Orange_UpperLeg_Tactical_v2 (Autodesk Fusion 360 design; units mm, degrees)
part number: 2026-11-06-02-17-48-614
Autodesk Fusion 360 part; units mm, degrees
ref_plane "WorkPlane1" through (0, 34.28, 0) normal (0, 1, 0) x (0, 0, 1)
sketch "HipShield" plane through (0, 34.28, 0) normal (0, 1, 0) x (1, 0, 0)
  line L0 (-12.447, 47.15) -> (-12.447, 26)
  line L1 (-12.447, 26) -> (-3.5, 16.67)
  line L2 (-3.5, 16.67) -> (4.16, 16.67)
  line L3 (4.16, 16.67) -> (7.87, 20.38)
  line L4 (7.87, 20.38) -> (7.87, 47.15)
  line L5 (7.87, 47.15) -> (-12.447, 47.15)
extrude "HipShield (1)" add sketch "HipShield" along normal blind 5.078 makes body 1
ref_plane "WorkPlane2" through (-12.447, 0, 0) normal (1, 0, 0) x (0, 1, 0)
sketch "ThighPanel" plane through (-12.447, 0, 0) normal (1, 0, 0) x (0, 0, -1)
  line L0 (66.2, 17.86) -> (56, 39.358)
  line L1 (56, 39.358) -> (42.07, 39.358)
  line L2 (42.07, 39.358) -> (42.07, 25)
  line L3 (42.07, 25) -> (39.31, 19.5)
  line L4 (39.31, 19.5) -> (39.31, 11.6)
  line L5 (39.31, 11.6) -> (44, 8.88)
  line L6 (44, 8.88) -> (62.48, 8.88)
  line L7 (62.48, 8.88) -> (66.2, 12.6)
  line L8 (66.2, 12.6) -> (66.2, 17.86)
extrude "ThighPanel (1)" add sketch "ThighPanel" along normal blind 5.077 bodies 1
ref_plane "WorkPlane3" through (0, 0, -47.15) normal (0, 0, 1) x (1, 0, 0)
sketch "InnerWeb" plane through (0, 0, -47.15) normal (0, 0, 1) x (1, 0, 0)
  line L0 (-7.37, 20) -> (-7.37, 36)
  line L1 (-7.37, 36) -> (7.87, 36)
  line L2 (7.87, 36) -> (7.87, 34.28)
  line L3 (7.87, 34.28) -> (-7.37, 20)
extrude "InnerWeb (1)" add sketch "InnerWeb" along normal blind 5.08 bodies 1
fillet "InnerCornerR2" radius 2 1 edges at (-2.2885, 34.28, -42.07) on bodies 1
ref_plane "WorkPlane4" through (-9.691, 0, 0) normal (1, 0, 0) x (0, 1, 0)
sketch "KneePocketSlot" plane through (-9.691, 0, 0) normal (1, 0, 0) x (0, 0, -1)
  arc A0 (59.5197, 11.6504) -> (59.5039, 19.1542) centre (59.8276, 15.403) ccw
  arc A1 (43.2874, 17.7552) -> (43.2975, 12.9812) centre (43.4933, 15.3687) ccw
  line L0 (59.5039, 19.1542) -> (43.2874, 17.7552)
  line L1 (43.2975, 12.9812) -> (59.5197, 11.6504)
extrude "KneePocketSlot (1)" cut sketch "KneePocketSlot" along normal blind 19.691 bodies 1
ref_plane "WorkPlane5" through (0, 30, 0) normal (0, 1, 0) x (0, 0, 1)
sketch "HipPocket" plane through (0, 30, 0) normal (0, 1, 0) x (1, 0, 0)
  arc A0 (-2.467, 23.3477) -> (5.5136, 23.3479) centre (1.5233, 23.0168) ccw
  arc A1 (4.166, 39.5876) -> (-1.1203, 39.5874) centre (1.5229, 39.3682) ccw
  line L0 (-2.467, 23.3477) -> (-1.1203, 39.5874)
  line L1 (4.166, 39.5876) -> (5.5136, 23.3479)
extrude "HipPocket (1)" cut sketch "HipPocket" along normal blind 6.691 bodies 1
ref_plane "WorkPlane6" through (1.52, 0, 0) normal (1, 0, 0) x (0, 1, 0)
sketch "HipHubRev" plane through (1.52, 0, 0) normal (1, 0, 0) x (0, 0, -1)
  line L0 (23.02, 36.691) -> (23.02, 37.834)
  line L1 (23.02, 37.834) -> (29.36, 37.834)
  line L2 (29.36, 37.834) -> (29.52, 37.667)
  line L3 (29.52, 37.667) -> (29.72, 37.472)
  line L4 (29.72, 37.472) -> (29.92, 37.317)
  line L5 (29.92, 37.317) -> (30.12, 37.178)
  line L6 (30.12, 37.178) -> (30.32, 37.066)
  line L7 (30.32, 37.066) -> (30.52, 36.965)
  line L8 (30.52, 36.965) -> (30.72, 36.889)
  line L9 (30.72, 36.889) -> (30.92, 36.818)
  line L10 (30.92, 36.818) -> (31.22, 36.751)
  line L11 (31.22, 36.751) -> (31.52, 36.711)
  line L12 (31.52, 36.711) -> (31.82, 36.691)
  line L13 (31.82, 36.691) -> (31.82, 36.691)
  line L14 (31.82, 36.691) -> (23.02, 36.691)
  line L15 (23.02, 30) -> (23.02, 45) construction
revolve "HipHubRev (1)" add sketch "HipHubRev" angle 360 about axis through (1.52, 30, -23.02) along (0, 1, 0) separate body makes body 2
ref_plane "WorkPlane7" through (0, 36, 0) normal (0, 1, 0) x (0, 0, 1)
sketch "HipHubPrism" plane through (0, 36, 0) normal (0, 1, 0) x (1, 0, 0)
  arc A0 (-2.467, 23.3477) -> (5.5136, 23.3479) centre (1.5233, 23.0168) ccw
  arc A1 (4.166, 39.5876) -> (-1.1203, 39.5874) centre (1.5229, 39.3682) ccw
  line L0 (-2.467, 23.3477) -> (-1.1203, 39.5874)
  line L1 (4.166, 39.5876) -> (5.5136, 23.3479)
extrude "HipHubPrism (1)" add sketch "HipHubPrism" along normal blind 2.2 separate body makes body 3
combine "HipHubIntersect" operation intersect target body 2 tool bodies 3
combine "HipHubCut" operation cut target body 1 tool bodies 2
ref_plane "WorkPlane8" through (0, 15.41, 0) normal (0, 1, 0) x (0, 0, 1)
sketch "KneeHubRev" plane through (0, 15.41, 0) normal (0, 1, 0) x (1, 0, 0)
  line L0 (-9.691, 59.85) -> (-10.834, 59.85)
  line L1 (-10.834, 59.85) -> (-10.834, 53.51)
  line L2 (-10.834, 53.51) -> (-10.667, 53.35)
  line L3 (-10.667, 53.35) -> (-10.472, 53.15)
  line L4 (-10.472, 53.15) -> (-10.317, 52.95)
  line L5 (-10.317, 52.95) -> (-10.178, 52.75)
  line L6 (-10.178, 52.75) -> (-10.066, 52.55)
  line L7 (-10.066, 52.55) -> (-9.965, 52.35)
  line L8 (-9.965, 52.35) -> (-9.889, 52.15)
  line L9 (-9.889, 52.15) -> (-9.818, 51.95)
  line L10 (-9.818, 51.95) -> (-9.751, 51.65)
  line L11 (-9.751, 51.65) -> (-9.711, 51.35)
  line L12 (-9.711, 51.35) -> (-9.691, 51.05)
  line L13 (-9.691, 51.05) -> (-9.691, 51.05)
  line L14 (-9.691, 51.05) -> (-9.691, 59.85)
  line L15 (-14, 59.85) -> (-5, 59.85) construction
revolve "KneeHubRev (1)" add sketch "KneeHubRev" angle 360 about axis through (-14, 15.41, -59.85) along (1, 0, 0) separate body makes body 4
ref_plane "WorkPlane9" through (-9.2, 0, 0) normal (1, 0, 0) x (0, 1, 0)
sketch "KneeHubPrism" plane through (-9.2, 0, 0) normal (1, 0, 0) x (0, 0, -1)
  arc A0 (59.5197, 11.6504) -> (59.5039, 19.1542) centre (59.8276, 15.403) ccw
  arc A1 (43.2874, 17.7552) -> (43.2975, 12.9812) centre (43.4933, 15.3687) ccw
  line L0 (59.5039, 19.1542) -> (43.2874, 17.7552)
  line L1 (43.2975, 12.9812) -> (59.5197, 11.6504)
extrude "KneeHubPrism (1)" add sketch "KneeHubPrism" against normal blind 2 separate body makes body 5
combine "KneeHubIntersect" operation intersect target body 4 tool bodies 5
combine "KneeHubCut" operation cut target body 1 tool bodies 4
fillet "HipMouthR125" radius 1.25 30 edges at (-1.0887, 34.28, -39.8307) (-1.7936, 34.28, -31.4676) (1.5234, 34.28, -19.0128) (4.8398, 34.28, -31.4677) (4.1345, 34.28, -39.8308) (1.5229, 32.7224, -42.0205) (-1.7936, 34.28, -31.4676) (1.5234, 34.28, -19.0128) (4.8398, 34.28, -31.4677) (4.1345, 34.28, -39.8308) (1.5229, 32.7224, -42.0205) (-1.0887, 34.28, -39.8307) (1.5234, 34.28, -19.0128) (4.8398, 34.28, -31.4677) (4.1345, 34.28, -39.8308) (1.5229, 32.7224, -42.0205) (-1.0887, 34.28, -39.8307) (-1.7936, 34.28, -31.4676) (4.8398, 34.28, -31.4677) (4.1345, 34.28, -39.8308) (1.5229, 32.7224, -42.0205) (-1.0887, 34.28, -39.8307) (-1.7936, 34.28, -31.4676) (1.5234, 34.28, -19.0128) (4.1345, 34.28, -39.8308) (1.5229, 32.7224, -42.0205) (-1.0887, 34.28, -39.8307) (-1.7936, 34.28, -31.4676) (1.5234, 34.28, -19.0128) (4.8398, 34.28, -31.4677) on bodies 1
fillet "KneeMouthR125" radius 1.25 16 edges at (-7.37, 15.3636, -41.0979) (-7.37, 18.4547, -51.3957) (-7.37, 15.4109, -63.5927) (-7.37, 12.3158, -51.4086) (-7.37, 18.4547, -51.3957) (-7.37, 15.4109, -63.5927) (-7.37, 12.3158, -51.4086) (-7.37, 15.3636, -41.0979) (-7.37, 15.4109, -63.5927) (-7.37, 12.3158, -51.4086) (-7.37, 15.3636, -41.0979) (-7.37, 18.4547, -51.3957) (-7.37, 12.3158, -51.4086) (-7.37, 15.3636, -41.0979) (-7.37, 18.4547, -51.3957) (-7.37, 15.4109, -63.5927) on bodies 1
chamfer "BottomRightBevel" distance 4 angle 45 2 edges at (0.25, 27.14, -47.15) (7.87, 36.819, -47.15) tangent chain off on bodies 1
chamfer "BladeBevels" distance 1.4 angle 45 20 edges at (5.87, 39.358, -45.15) (-1.75, 39.358, -47.15) (-7.37, 39.358, -51.575) (-9.9085, 39.358, -56) (-12.447, 39.358, -41) (-7.9735, 39.358, -21.335) (0.33, 39.358, -16.67) (6.015, 39.358, -18.525) (7.87, 39.358, -31.765) (-12.447, 34.28, -33.035) (-12.447, 36.819, -26) (-12.447, 28.609, -61.1) (-12.447, 15.23, -66.2) (-12.447, 10.74, -64.34) (-12.447, 8.88, -53.24) (-12.447, 10.24, -41.655) (-12.447, 15.55, -39.31) (-12.447, 22.25, -40.69) (-12.447, 28.64, -42.07) (-12.447, 33.6942, -41.4842) tangent chain off on bodies 1
ref_plane "WorkPlane10" through (-13.447, 0, 0) normal (1, 0, 0) x (0, 1, 0)
sketch "PanelWindow0" plane through (-13.447, 0, 0) normal (1, 0, 0) x (0, 0, -1)
  line L0 (48, 34.066) -> (56.896, 24.246)
  line L1 (56.896, 24.246) -> (48, 22.4)
  line L2 (48, 22.4) -> (48, 34.066)
extrude "PanelWindow0 (1)" cut sketch "PanelWindow0" along normal blind 6.077 bodies 1
ref_plane "WorkPlane11" through (-13.447, 0, 0) normal (1, 0, 0) x (0, 1, 0)
sketch "PanelWindow1" plane through (-13.447, 0, 0) normal (1, 0, 0) x (0, 0, -1)
  line L0 (53.1, 36.3) -> (56.417, 29.243)
  line L1 (56.417, 29.243) -> (50.024, 36.3)
  line L2 (50.024, 36.3) -> (53.1, 36.3)
extrude "PanelWindow1 (1)" cut sketch "PanelWindow1" along normal blind 6.077 bodies 1
ref_plane "WorkPlane12" through (0, 30, 0) normal (0, 1, 0) x (0, 0, 1)
sketch "HipHoleC" plane through (0, 30, 0) normal (0, 1, 0) x (1, 0, 0)
  circle A0 centre (1.52, 23.02) radius 1.248
extrude "HipHoleC (1)" cut sketch "HipHoleC" along normal blind 11 bodies 1
ref_plane "WorkPlane13" through (0, 30, 0) normal (0, 1, 0) x (0, 0, 1)
sketch "HipHoleL" plane through (0, 30, 0) normal (0, 1, 0) x (1, 0, 0)
  circle A0 centre (1.52, 34.45) radius 1.248
extrude "HipHoleL (1)" cut sketch "HipHoleL" along normal blind 11 bodies 1
ref_plane "WorkPlane14" through (-14, 0, 0) normal (1, 0, 0) x (0, 1, 0)
sketch "KneeHoleC" plane through (-14, 0, 0) normal (1, 0, 0) x (0, 0, -1)
  circle A0 centre (59.85, 15.23) radius 1.248
extrude "KneeHoleC (1)" cut sketch "KneeHoleC" along normal blind 8 bodies 1
ref_plane "WorkPlane15" through (-14, 0, 0) normal (1, 0, 0) x (0, 1, 0)
sketch "KneeHoleL" plane through (-14, 0, 0) normal (1, 0, 0) x (0, 0, -1)
  circle A0 centre (48.42, 15.23) radius 1.248
extrude "KneeHoleL (1)" cut sketch "KneeHoleL" along normal blind 8 bodies 1
ref_plane "WorkPlane16" through (1.52, 0, 0) normal (1, 0, 0) x (0, 1, 0)
sketch "HipCsC" plane through (1.52, 0, 0) normal (1, 0, 0) x (0, 0, -1)
  line L0 (23.02, 39.658) -> (18.9237, 39.658)
  line L1 (18.9237, 39.658) -> (19.4, 39.358)
  line L2 (19.4, 39.358) -> (21.77, 37.865)
  line L3 (21.77, 37.865) -> (23.02, 37.865)
  line L4 (23.02, 37.865) -> (23.02, 39.658)
  line L5 (23.02, 30) -> (23.02, 45) construction
revolve "HipCsC (1)" cut sketch "HipCsC" angle 360 about axis through (1.52, 30, -23.02) along (0, 1, 0) bodies 1
ref_plane "WorkPlane17" through (1.52, 0, 0) normal (1, 0, 0) x (0, 1, 0)
sketch "HipCsL" plane through (1.52, 0, 0) normal (1, 0, 0) x (0, 0, -1)
  line L0 (34.45, 39.658) -> (30.946, 39.658)
  line L1 (30.946, 39.658) -> (31.672, 39.358)
  line L2 (31.672, 39.358) -> (32.9754, 38.8194)
  line L3 (32.9754, 38.8194) -> (33.2, 38.597)
  line L4 (33.2, 38.597) -> (34.45, 38.597)
  line L5 (34.45, 38.597) -> (34.45, 39.658)
  line L6 (34.45, 30) -> (34.45, 45) construction
revolve "HipCsL (1)" cut sketch "HipCsL" angle 360 about axis through (1.52, 30, -34.45) along (0, 1, 0) bodies 1
ref_plane "WorkPlane18" through (0, 15.23, 0) normal (0, 1, 0) x (0, 0, 1)
sketch "KneeCsC" plane through (0, 15.23, 0) normal (0, 1, 0) x (1, 0, 0)
  line L0 (-12.747, 59.85) -> (-12.747, 55.7537)
  line L1 (-12.747, 55.7538) -> (-12.447, 56.23)
  line L2 (-12.447, 56.23) -> (-10.954, 58.6)
  line L3 (-10.954, 58.6) -> (-10.954, 59.85)
  line L4 (-10.954, 59.85) -> (-12.747, 59.85)
  line L5 (-14, 59.85) -> (-5, 59.85) construction
revolve "KneeCsC (1)" cut sketch "KneeCsC" angle 360 about axis through (-14, 15.23, -59.85) along (1, 0, 0) bodies 1
ref_plane "WorkPlane19" through (0, 15.23, 0) normal (0, 1, 0) x (0, 0, 1)
sketch "KneeCsL" plane through (0, 15.23, 0) normal (0, 1, 0) x (1, 0, 0)
  line L0 (-12.747, 48.42) -> (-12.747, 44.916)
  line L1 (-12.747, 44.916) -> (-12.447, 45.642)
  line L2 (-12.447, 45.642) -> (-11.9084, 46.9454)
  line L3 (-11.9084, 46.9454) -> (-11.686, 47.17)
  line L4 (-11.686, 47.17) -> (-11.686, 48.42)
  line L5 (-11.686, 48.42) -> (-12.747, 48.42)
  line L6 (-14, 48.42) -> (-5, 48.42) construction
revolve "KneeCsL (1)" cut sketch "KneeCsL" angle 360 about axis through (-14, 15.23, -48.42) along (1, 0, 0) bodies 1
ref_plane "WorkPlane29" through (0, 39.358, 0) normal (0, 1, 0) x (0, 0, 1)
sketch "label_L1" plane through (0, 39.358, 0) normal (0, 1, 0) x (1, 0, 0)
  line L0 (-9.65, 39.41) -> (-9.65, 31.79) construction
  line L1 (-9.65, 31.79) -> (-4.55, 31.79) construction
  line L2 (-4.55, 31.79) -> (-4.55, 39.41) construction
  line L3 (-4.55, 39.41) -> (-9.65, 39.41) construction
  dimension "d137" = 4.5
  dimension "d138" = 0
  text T0 "L1" font "Arial Black" height 4.5 align centre middle in box 7.62 x 5.1 at (-9.65, 39.41) x (0, -1) y (1, 0) spacing 1 kerned
extrude "LabelCut" cut sketch "label_L1" against normal blind 0.5 text T0 bodies 1
equation "d138 = 'L1'"
named bodies: "UpperLeg_L1"
